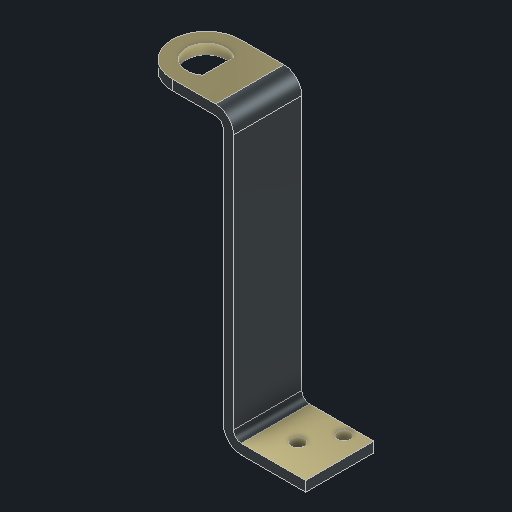
# Autodesk Inventor part: s1101mfd1722
Saved by Autodesk Inventor 2027.1 (Build 311270010, 270A)
## iProperties
Created: 2026-10-31
Part Number: s1101mfd1722
Material: Generic
Document SubType Name: Modeling
Designer: User
Density: 1 g/cm^3
Appearance: Iron Gray
Author: User
Autodesk Inventor part; units mm, degrees
ref_plane "YZ Plane" through (0, 0, 0) normal (1, 0, 0) x (0, 1, 0)
ref_plane "XY Plane" through (0, 0, 0) normal (0, 0, 1) x (1, 0, 0)
sketch "Sketch1" plane through (0, 0, 0) normal (0, 0, 1) x (1, 0, 0)
  line L0 (-31.242, 95.25) -> (0, 95.25)
  line L1 (0, 95.25) -> (0, 3.302)
  line L2 (0, 3.302) -> (23.622, 3.302)
  line L3 (23.622, 3.302) -> (23.622, 0)
  line L4 (23.622, 0) -> (-3.302, 0)
  line L5 (-3.302, 0) -> (-3.302, 91.948)
  line L6 (-3.302, 91.948) -> (-31.242, 91.948)
  line L7 (-31.242, 91.948) -> (-31.242, 95.25)
  constraints: 16 end point
extrude "Extrusion1" add sketch "Sketch1" along normal mid plane 22.352
ref_plane "Work Plane1" through (0, 88.9, 0) normal (0, 1, 0) x (-1, 0, 0)
sketch "Sketch3" plane through (0, 88.9, 0) normal (0, 1, 0) x (-1, 0, 0)
  arc A0 (16.1544, -5.1305) -> (16.1544, 5.1305) centre (20.066, 0) ccw
  line L0 (16.1544, -5.1305) -> (16.1544, 5.1305)
  constraints: 2 end point, 2 point on circle, 1 centre point
extrude "Extrusion2" cut sketch "Sketch3" along normal blind 12.7
sketch "Sketch4" plane through (0, 0, 0) normal (0, 1, 0) x (-1, 0, 0)
  circle A0 centre (-11.43, 1.5875) radius 2.1082
  circle A1 centre (-17.018, -7.9375) radius 2.1082
  constraints: 2 centre point
extrude "Extrusion3" cut sketch "Sketch4" along normal mid plane 12.7
fillet "Fillet1" radius 2.54 2 edges at (0, 3.302, 0) (-3.302, 91.948, 0)
fillet "Fillet2" radius 5.842 2 edges at (0, 95.25, 0) (-3.302, 0, 0)
fillet "Fillet3" radius 11.1506 2 edges at (-31.242, 93.599, -11.176) (-31.242, 93.599, 11.176)
body "Solid1"
